Autodesk Fusion 360 part; units mm, degrees
(part 2 of 2)
sketch "Sketch26" plane through (0, 0, 0) normal (0, 0, 1) x (-1, 0, 0)
  circle A0 centre (0.0425, -54.0357) radius 1.85
  circle A1 centre (-48.989, 56.0983) radius 1.9
  circle A2 centre (49.1041, 56.0966) radius 1.9
  circle A3 centre (-49.0489, -56.0992) radius 1.9
  circle A4 centre (49.1247, -56.1029) radius 1.9
  circle A5 centre (51.1884, 99.1347) radius 1.85
  circle A6 centre (75.5913, 102.5343) radius 0.8
  circle A7 centre (-90.0969, -79.2783) radius 0.8
  circle A8 centre (90.1725, -79.2921) radius 0.8
  circle A9 centre (90.1026, 79.3599) radius 0.8
  circle A10 centre (51.1939, -99.1597) radius 1.85
  circle A11 centre (0.0682, 99.4831) radius 1.85
  circle A12 centre (-108.7523, -13.6846) radius 0.8
  circle A13 centre (-51.0571, 99.1371) radius 1.85
  circle A14 centre (75.6553, -102.4768) radius 0.8
  circle A15 centre (108.8477, -13.679) radius 0.8
  circle A16 centre (-89.9874, 79.369) radius 0.8
  circle A17 centre (-51.1366, -99.1566) radius 1.85
  circle A18 centre (108.8477, 13.668) radius 0.8
  circle A19 centre (-75.5979, -102.4631) radius 0.8
  circle A20 centre (-75.515, 102.4682) radius 0.8
  circle A21 centre (-108.7523, 13.7506) radius 0.8
  line L0 (-69.3323, -105.7468) -> (-36.906, -110.0169)
  line L1 (-36.906, -110.0169) -> (36.954, -110.0169)
  line L2 (36.954, -110.0169) -> (69.3862, -105.7589)
  arc A22 (75.995, -107.1982) -> (69.3862, -105.7589) centre (70.688, -115.6738) ccw
  line L3 (75.995, -107.1982) -> (91.7226, -117.0462)
  arc A23 (91.7226, -117.0462) -> (101.3705, -114.8282) centre (95.4376, -111.1132) ccw
  line L4 (101.3705, -114.8282) -> (101.7116, -114.2834)
  line L5 (101.7116, -114.2834) -> (70.2248, -94.5678)
  line L6 (70.2248, -94.5678) -> (80.686, -77.8607)
  line L7 (80.686, -77.8607) -> (112.1728, -97.5763)
  line L8 (112.1728, -97.5763) -> (112.5139, -97.0316)
  arc A24 (112.5139, -97.0316) -> (110.2959, -87.3838) centre (106.581, -93.3167) ccw
  line L9 (110.2959, -87.3838) -> (94.5669, -77.535)
  arc A25 (90.3869, -72.2209) -> (94.5669, -77.535) centre (99.874, -69.0595) ccw
  line L10 (90.3869, -72.2209) -> (80.0477, -41.1942)
  line L11 (80.0477, -41.1942) -> (105.2515, -19.8703)
  arc A26 (111.7105, -17.5046) -> (105.2515, -19.8703) centre (111.7105, -27.5046) ccw
  line L12 (111.7105, -17.5046) -> (130.0589, -17.5046)
  arc A27 (130.0589, -17.5046) -> (137.0576, -10.3672) centre (130.0589, -10.5046) ccw
  line L13 (137.0576, -10.3672) -> (137.0477, -9.8646)
  line L14 (137.0477, -9.8646) -> (100.0477, -9.8646)
  line L15 (100.0477, -9.8646) -> (100.0477, 9.8404)
  line L16 (100.0477, 9.8404) -> (137.0477, 9.8404)
  line L17 (137.0477, 9.8404) -> (137.0579, 10.3626)
  arc A28 (137.0579, 10.3626) -> (130.0593, 17.4996) centre (130.0593, 10.4996) ccw
  line L18 (130.0593, 17.4996) -> (111.707, 17.4996)
  arc A29 (105.2527, 19.8614) -> (111.707, 17.4996) centre (111.707, 27.4996) ccw
  line L19 (105.2527, 19.8614) -> (80.0477, 41.1594)
  line L20 (80.0477, 41.1594) -> (90.3683, 72.2128)
  arc A30 (94.551, 77.5346) -> (90.3683, 72.2128) centre (99.8579, 69.059) ccw
  line L21 (94.551, 77.5346) -> (110.2761, 87.3808)
  arc A31 (110.2761, 87.3808) -> (112.4942, 97.0286) centre (106.5612, 93.3137) ccw
  line L22 (112.4942, 97.0286) -> (112.1557, 97.5692)
  line L23 (112.1557, 97.5692) -> (80.6688, 77.8538)
  line L24 (80.6688, 77.8538) -> (70.2143, 94.5503)
  line L25 (70.2143, 94.5503) -> (101.7012, 114.2657)
  line L26 (101.7012, 114.2657) -> (101.3627, 114.8063)
  arc A32 (101.3627, 114.8063) -> (91.7149, 117.0244) centre (95.4298, 111.0915) ccw
  line L27 (91.7149, 117.0244) -> (75.9857, 107.1756)
  arc A33 (69.38, 105.7359) -> (75.9857, 107.1756) centre (70.6787, 115.6512) ccw
  line L28 (69.38, 105.7359) -> (36.954, 109.9831)
  line L29 (36.954, 109.9831) -> (-0.4655, 114.9106)
  line L30 (-0.4655, 114.9106) -> (-36.8155, 109.9831)
  line L31 (-36.8155, 109.9831) -> (-69.2461, 105.7456)
  arc A34 (-75.8525, 107.1881) -> (-69.2461, 105.7456) centre (-70.5417, 115.6613) ccw
  line L32 (-75.8525, 107.1881) -> (-91.5766, 117.0435)
  arc A35 (-91.5766, 117.0435) -> (-101.2254, 114.8298) centre (-95.2942, 111.1123) ccw
  line L33 (-101.2254, 114.8298) -> (-101.5653, 114.2875)
  line L34 (-101.5653, 114.2875) -> (-70.0873, 94.5579)
  line L35 (-70.0873, 94.5579) -> (-80.5522, 77.8615)
  line L36 (-80.5522, 77.8615) -> (-112.0302, 97.591)
  line L37 (-112.0302, 97.591) -> (-112.3701, 97.0487)
  arc A36 (-112.3701, 97.0487) -> (-110.1564, 87.3999) centre (-106.4389, 93.3312) ccw
  line L38 (-110.1564, 87.3999) -> (-94.4364, 77.547)
  arc A37 (-90.2557, 72.2221) -> (-94.4364, 77.547) centre (-99.7471, 69.0738) ccw
  line L39 (-90.2557, 72.2221) -> (-79.9523, 41.1594)
  line L40 (-79.9523, 41.1594) -> (-105.1606, 19.861)
  arc A38 (-111.6069, 17.4996) -> (-105.1606, 19.861) centre (-111.6145, 27.4996) ccw
  line L41 (-111.6069, 17.4996) -> (-130.1099, 17.4857)
  arc A39 (-130.1099, 17.4857) -> (-137.1046, 10.4595) centre (-130.1047, 10.4857) ccw
  line L42 (-137.1046, 10.4595) -> (-137.1023, 9.8404)
  line L43 (-137.1023, 9.8404) -> (-99.9523, 9.8404)
  line L44 (-99.9523, 9.8404) -> (-99.9523, -9.8646)
  line L45 (-99.9523, -9.8646) -> (-137.1023, -9.8646)
  line L46 (-137.1023, -9.8646) -> (-137.0948, -10.2221)
  arc A40 (-137.0948, -10.2221) -> (-130.1562, -17.0751) centre (-130.0963, -10.0753) ccw
  line L47 (-130.1562, -17.0751) -> (-111.5933, -17.2339)
  arc A41 (-105.1837, -19.63) -> (-111.5933, -17.2339) centre (-111.6789, -27.2335) ccw
  line L48 (-105.1837, -19.63) -> (-79.9523, -41.1835)
  line L49 (-79.9523, -41.1835) -> (-90.3067, -72.2075)
  arc A42 (-94.4901, -77.5202) -> (-90.3067, -72.2075) centre (-99.7924, -69.0416) ccw
  line L50 (-94.4901, -77.5202) -> (-110.2242, -87.3598)
  arc A43 (-110.2242, -87.3598) -> (-112.4476, -97.0064) centre (-106.5126, -93.2948) ccw
  line L51 (-112.4476, -97.0064) -> (-112.1082, -97.549)
  line L52 (-112.1082, -97.549) -> (-80.6103, -77.8512)
  line L53 (-80.6103, -77.8512) -> (-70.1622, -94.5583)
  line L54 (-70.1622, -94.5583) -> (-101.6601, -114.2561)
  line L55 (-101.6601, -114.2561) -> (-101.3208, -114.7987)
  arc A44 (-101.3208, -114.7987) -> (-91.6742, -117.0222) centre (-95.3858, -111.0872) ccw
  line L56 (-91.6742, -117.0222) -> (-75.9402, -107.1826)
  arc A45 (-69.3323, -105.7468) -> (-75.9402, -107.1826) centre (-70.6379, -115.6612) ccw
  line L57 (-17.5, 10) -> (17.5, 10)
  line L58 (17.5, 10) -> (17.5, -10)
  line L59 (17.5, -10) -> (-17.5, -10)
  line L60 (-17.5, -10) -> (-17.5, 10)
  line L61 (-80.6103, -77.8512) -> (-88.1607, -65.7777)
  line L62 (-88.1607, -65.7777) -> (-79.9523, -41.1835)
  line L63 (-99.9523, -9.8646) -> (-99.9523, -24.0989)
  line L64 (-99.9523, -24.0989) -> (-79.9523, -41.1835)
  line L65 (-99.9523, 9.8404) -> (-99.9523, 24.2615)
  line L66 (-99.9523, 24.2615) -> (-79.9523, 41.1594)
  line L67 (-80.5522, 77.8615) -> (-88.1208, 65.7859)
  line L68 (-88.1208, 65.7859) -> (-79.9523, 41.1594)
  line L69 (-80.5522, 77.8615) -> (-62.5247, 106.6238)
  line L70 (-99.9523, -9.8646) -> (-99.9523, 9.8404)
  line L71 (-80.6103, -77.8512) -> (-62.6118, -106.6318)
  line L72 (-62.5247, 106.6238) -> (-0.4655, 114.9106)
  line L73 (70.2143, 94.5503) -> (62.6593, 106.6162)
  line L74 (62.6593, 106.6162) -> (-1.2851, 115.0366)
  line L75 (70.2143, 94.5503) -> (88.2298, 65.7783)
  line L76 (88.2298, 65.7783) -> (80.0477, 41.1594)
  line L77 (100.0477, 9.8404) -> (100.0477, 24.2596)
  line L78 (100.0477, 24.2596) -> (80.0477, 41.1594)
  line L79 (100.0477, 9.8404) -> (100.0477, -24.273)
  line L80 (100.0477, -24.273) -> (80.0477, -41.1942)
  line L81 (80.686, -77.8607) -> (88.244, -65.7903)
  line L82 (80.0477, -41.1942) -> (88.244, -65.7903)
  line L83 (80.686, -77.8607) -> (62.6649, -106.6413)
  line L84 (62.6649, -106.6413) -> (36.954, -110.0169)
  line L85 (36.954, -110.0169) -> (-36.906, -110.0169)
  line L86 (-62.6118, -106.6318) -> (-36.906, -110.0169)
  line L87 (-59.5353, 101.9786) -> (-0.3928, 109.8759)
  line L88 (-76.3156, 75.2061) -> (-59.5353, 101.9786)
  line L89 (-76.3156, 75.2061) -> (-82.6338, 65.1254)
  line L90 (-82.6338, 65.1254) -> (-74.1416, 39.5231)
  line L91 (-94.9523, 21.9403) -> (-74.1416, 39.5231)
  line L92 (-94.9523, 9.8404) -> (-94.9523, 21.9403)
  line L93 (-94.9523, -9.8646) -> (-94.9523, 9.8404)
  line L94 (-94.9523, -9.8646) -> (-94.9523, -21.7941)
  line L95 (-94.9523, -21.7941) -> (-74.1427, -39.5703)
  line L96 (-82.6717, -65.1249) -> (-74.1427, -39.5703)
  line L97 (-76.371, -75.2) -> (-82.6717, -65.1249)
  line L98 (-76.371, -75.2) -> (-59.6222, -101.9823)
  line L99 (-59.6222, -101.9823) -> (-36.5782, -105.0169)
  line L100 (36.6272, -105.0169) -> (-36.5782, -105.0169)
  line L101 (59.6777, -101.9906) -> (36.6272, -105.0169)
  line L102 (76.4482, -75.2072) -> (59.6777, -101.9906)
  line L103 (76.4482, -75.2072) -> (82.7552, -65.1347)
  line L104 (74.234, -39.5635) -> (82.7552, -65.1347)
  line L105 (95.0477, -21.9539) -> (74.234, -39.5635)
  line L106 (95.0477, 9.8404) -> (95.0477, -21.9539)
  line L107 (95.0477, 9.8404) -> (95.0477, 21.9385)
  line L108 (95.0477, 21.9385) -> (74.2355, 39.5247)
  line L109 (82.7423, 65.1206) -> (74.2355, 39.5247)
  line L110 (65.9765, 91.8968) -> (82.7423, 65.1206)
  line L111 (65.9765, 91.8968) -> (59.6714, 101.9665)
  line L112 (59.6714, 101.9665) -> (-0.3928, 109.8759)
  circle A46 centre (74.7552, -65.1347) radius 4
  circle A47 centre (74.7552, -65.1347) radius 1.9
  line L113 (-82.6717, -65.1249) -> (-74.6717, -65.1249)
  circle A48 centre (-74.6717, -65.1249) radius 4
  circle A49 centre (-74.6717, -65.1249) radius 1.9
  line L114 (82.7423, 65.1206) -> (74.7423, 65.1206)
  circle A50 centre (74.7423, 65.1206) radius 4
  circle A51 centre (74.7423, 65.1206) radius 1.9
  line L115 (-82.6338, 65.1254) -> (-74.6338, 65.1254)
  circle A52 centre (-74.6338, 65.1254) radius 4
  circle A53 centre (-74.6338, 65.1254) radius 1.9
  dimension "d348" = 5
  dimension "d351" = 8
  dimension "d352" = 8
  dimension "d353" = 3.8
  dimension "d354" = 8
  dimension "d355" = 8
  dimension "d356" = 3.8
  dimension "d357" = 8
  dimension "d358" = 8
  dimension "d359" = 3.8
  dimension "d360" = 8
  dimension "d361" = 8
  dimension "d362" = 3.8
  constraint coincident L52.end L53.start
  constraint coincident L49 L61.end
  constraint perpendicular L52 L61
  constraint coincident L48.end L49.start
  constraint coincident L44.end L45.start
  constraint coincident L48 L63.end
  constraint perpendicular L45 L63
  constraint coincident L43.end L44.start
  constraint coincident L40 L65.end
  constraint perpendicular L43 L65
  constraint coincident L39.end L40.start
  constraint coincident L35.end L36.start
  constraint coincident L39 L67.end
  constraint perpendicular L36 L67
  constraint coincident L31 L69.end
  constraint perpendicular L34 L69
  constraint coincident L0 L71.end
  constraint perpendicular L54 L71
  constraint coincident L29.end L30.start
  constraint coincident L24.end L25.start
  constraint coincident L28 L73.end
  constraint perpendicular L25 L73
  constraint parallel L29 L74
  constraint coincident L20 L75.end
  constraint perpendicular L23 L75
  constraint coincident L19.end L20.start
  constraint coincident L15.end L16.start
  constraint coincident L19 L77.end
  constraint perpendicular L16 L77
  constraint coincident L11 L79.end
  constraint parallel L15 L79
  constraint coincident L10.end L11.start
  constraint coincident L6.end L7.start
  constraint coincident L10 L81.end
  constraint perpendicular L7 L81
  constraint coincident L2 L83.end
  constraint perpendicular L5 L83
  constraint coincident L1.end L2.start
  constraint coincident L0.end L1.start
  constraint concentric A46 A47
  constraint horizontal L113
  constraint coincident L113.end A48.centre
  constraint concentric A48 A49
  constraint horizontal L114
  constraint coincident L114.end A50.centre
  constraint concentric A50 A51
  constraint horizontal L115
  constraint coincident L115.end A52.centre
  constraint concentric A52 A53
  measures "d351" distance of L103.end A46.centre
  measures "d352" diameter of A46
  measures "d353" diameter of A47
  measures "d354" distance of L96.start L113.end
  measures "d355" diameter of A48
  measures "d356" diameter of A49
  measures "d357" distance of L109.start L114.end
  measures "d358" diameter of A50
  measures "d359" diameter of A51
  measures "d360" distance of L89.end L115.end
  measures "d361" diameter of A52
  measures "d362" diameter of A53
extrude "Extrude38" add sketch "Sketch26" along normal blind 18 contours L0 L1 L2 L6 L10 L11 L15 L19 L20 L24 L28 L29 L30 L31 L35 L39 L40 L44 L48 L49 L53 L61 L62 L63 L64 L65 L66 L67 L68 L69 L70 L71 L73 L75 L76 L77 L78 L79 L80 L81 L82 L83 L84 L85 L86 bodies 1
extrude "Extrude39" add sketch "Sketch26" along normal blind 18 contours A46 | A48 | A50 | A52 bodies 1
